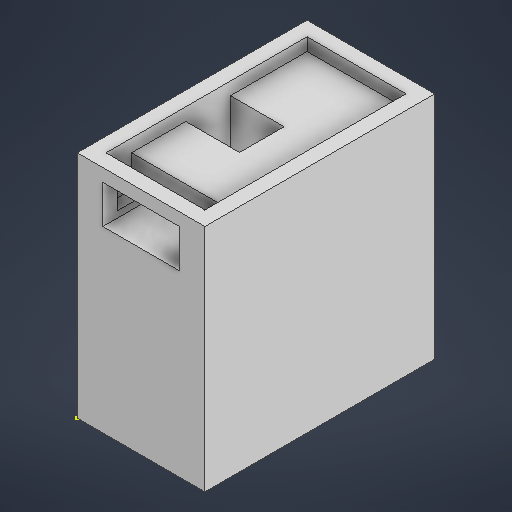
# Autodesk Inventor part: OPTYCZNY
Saved by Autodesk Inventor 2026.1 (Build 301233020, 233B)
## iProperties
Created: 2026-09-18
Part Number: OPTYCZNY
Material: Ogólny
Document SubType Name: Modeling
Designer: Bronh
Density: 1 g/cm^3
Appearance: Domyślna
Author: Bronh
Autodesk Inventor part; units mm, degrees
ref_plane "YZ Plane" through (0, 0, 0) normal (1, 0, 0) x (0, 1, 0)
ref_plane "XZ Plane" through (0, 0, 0) normal (0, 1, 0) x (-1, 0, 0)
ref_plane "XY Plane" through (0, 0, 0) normal (0, 0, 1) x (1, 0, 0)
sketch "Szkic1" plane through (0, 0, 0) normal (0, 0, 1) x (1, 0, 0)
  line L0 (0, 0) -> (20, 0)
  line L1 (20, 0) -> (20, 36)
  line L2 (20, 36) -> (0, 36)
  line L3 (0, 36) -> (0, 0)
  dimension "d0" = 20
  dimension "d1" = 36
  constraints: 8 end point, 2 parallel, 1 horizontal, 1 perpendicular
  measures "d0" distance of L2.end L1.end
  measures "d1" distance of L1.end L0.end
extrude "Wyciągnięcie proste1" add sketch "Szkic1" along normal blind 36
sketch "Szkic2" plane through (0, 36, 0) normal (0, 1, 0) x (1, 0, 0)
  line L0 (17.75, -2.25) -> (2.25, -2.25)
  line L1 (2.25, -2.25) -> (2.25, -33.75)
  line L2 (2.25, -33.75) -> (17.75, -33.75)
  line L3 (17.75, -33.75) -> (17.75, -2.25)
  line L4 (20, 0) -> (20, -36) projected
  line L5 (20, -36) -> (0, -36) projected
  point P0 (0, 0)
  point P1 (10, -33.75)
  dimension "d4" = 31.5
  dimension "d5" = 15.5
  dimension "d6" = 2.25
  dimension "d7" = 2.25
  constraints: 8 end point, 2 parallel, 1 horizontal, 1 midpoint, 1 perpendicular
  measures "d4" distance of L2.end L0.start
  measures "d5" distance of L1.end L2.end
  measures "d6" distance between parallel lines of L3 L4
  measures "d7" distance from line of L5 point (10, -33.75)
extrude "Wyciągnięcie proste2" cut sketch "Szkic2" against normal blind 2
sketch "Szkic3" plane through (0, 34, 0) normal (0, 1, 0) x (1, 0, 0)
  line L0 (10.665, -14.25) -> (2.25, -14.25)
  line L1 (2.25, -14.25) -> (2.25, -21.25)
  line L2 (2.25, -21.25) -> (10.665, -21.25)
  line L3 (10.665, -21.25) -> (10.665, -14.25)
  line L4 (2.25, -2.25) -> (17.75, -2.25) projected
  line L5 (2.25, -33.75) -> (2.25, -2.25) projected
  point P0 (0, 0)
  dimension "d10" = 8.415
  dimension "d11" = 7
  dimension "d12" = 12
  dimension "d25" = 0
  constraints: 8 end point, 2 parallel, 1 horizontal, 1 perpendicular
  measures "d10" distance of L2.end L1.end
  measures "d11" distance of L1.end L0.end
  measures "d12" distance between parallel lines of L4 L0
  measures "d25" distance between parallel lines of L5 L1
extrude "Wyciągnięcie proste3" cut sketch "Szkic3" against normal blind 7
sketch "Szkic4" plane through (0, 34, 0) normal (0, 1, 0) x (1, 0, 0)
  line L0 (17.75, -33.75) -> (2.25, -33.75) projected
  line L1 (17.25, -29.75) -> (2.25, -29.75)
  line L2 (2.25, -29.75) -> (2.25, -33.75)
  line L3 (2.25, -33.75) -> (17.25, -33.75)
  line L4 (17.25, -33.75) -> (17.25, -29.75)
  point P0 (0, 0)
  point P1 (17.25, -33.75)
  dimension "d15" = 4
  dimension "d16" = 15
  constraints: 8 end point, 2 parallel, 1 horizontal, 1 perpendicular
  measures "d15" distance of L3.end L1.start
  measures "d16" distance of L1.start L1.end
extrude "Wyciągnięcie proste4" cut sketch "Szkic4" against normal blind 5
sketch "Szkic5" plane through (0, 0, 36) normal (0, 0, 1) x (1, 0, 0)
  point P0 (0, 0)
sketch "Szkic6" plane through (0, 0, 36) normal (0, 0, 1) x (1, 0, 0)
  line L0 (4, 34) -> (16, 34)
  line L1 (16, 34) -> (16, 28)
  line L2 (16, 28) -> (4, 28)
  line L3 (4, 28) -> (4, 34)
  line L4 (0, 36) -> (0, 0) projected
  line L5 (20, 0) -> (20, 36) projected
  line L6 (20, 36) -> (0, 36) projected
  point P0 (16, 31)
  dimension "d19" = 4
  dimension "d20" = 4
  dimension "d21" = 6
  dimension "d22" = 2
  constraints: 8 end point, 2 parallel, 1 horizontal, 1 midpoint, 1 perpendicular
  measures "d19" distance between parallel lines of L4 L3
  measures "d20" distance from line of L5 point (16, 31)
  measures "d21" distance of L0.end L1.end
  measures "d22" distance between parallel lines of L0 L6
extrude "Wyciągnięcie proste5" cut sketch "Szkic6" against normal blind 6.25
